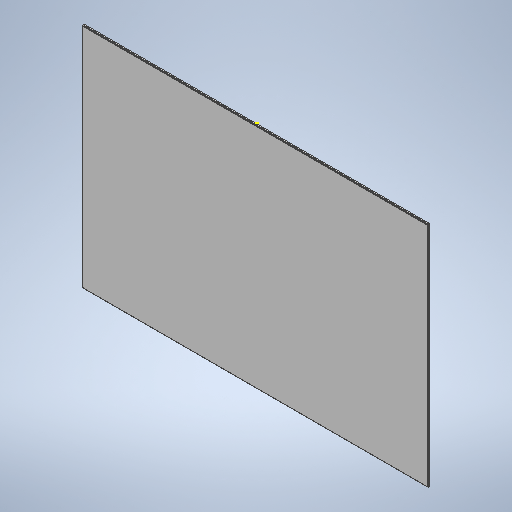
# Autodesk Inventor part: Tampa
Saved by Autodesk Inventor 2025.1 (Build 291241020, 241B)
## iProperties
Created: 2024-11-19
Part Number: Tampa
Material: Genérico
Document SubType Name: Modeling
Designer: Alecs
Density: 1 g/cm^3
Appearance: Padrão
Author: Alecs
Autodesk Inventor part; units mm, degrees
ref_plane "YZ Plane" through (0, 0, 0) normal (1, 0, 0) x (0, 1, 0)
ref_plane "XZ Plane" through (0, 0, 0) normal (0, 1, 0) x (-1, 0, 0)
ref_plane "XY Plane" through (0, 0, 0) normal (0, 0, 1) x (1, 0, 0)
sketch "Esboço1" plane through (0, 0, 0) normal (0, 0, 1) x (1, 0, 0)
  line L0 (322.5, 212.5) -> (-322.5, 212.5)
  line L1 (-322.5, 212.5) -> (-322.5, -212.5)
  line L2 (-322.5, -212.5) -> (322.5, -212.5)
  line L3 (322.5, -212.5) -> (322.5, 212.5)
  line L4 (322.5, 212.5) -> (-322.5, -212.5) construction
  line L5 (-322.5, 212.5) -> (322.5, -212.5) construction
  point P0 (0, 0)
  dimension "d0" = 425
  dimension "d1" = 645
  constraints: 12 end point, 2 midpoint, 2 parallel, 1 horizontal, 1 perpendicular
  measures "d0" distance of L0.end L1.end
  measures "d1" distance of L0.start L0.end
extrude "Extrusão1" add sketch "Esboço1" along normal blind 2
sketch "Esboço2" plane through (0, 0, 2) normal (0, 0, 1) x (1, 0, 0)
  line L0 (320.85, 211) -> (-320.85, 211)
  line L1 (-320.85, 211) -> (-320.85, -211)
  line L2 (-320.85, -211) -> (320.85, -211)
  line L3 (320.85, -211) -> (320.85, 211)
  line L4 (320.85, 211) -> (-320.85, -211) construction
  line L5 (-320.85, 211) -> (320.85, -211) construction
  point P0 (0, 0)
  dimension "d4" = 422
  dimension "d5" = 641.7
  constraints: 12 end point, 2 midpoint, 2 parallel, 1 horizontal, 1 perpendicular
  measures "d4" distance of L0.end L1.end
  measures "d5" distance of L1.end L2.end
extrude "Extrusão2" add sketch "Esboço2" along normal blind 1.175
fillet "Arredondamento1" radius 1 8 edges at (322.5, 212.5, 1) (320.85, 211, 2.5875) (-322.5, 212.5, 1) (-320.85, 211, 2.5875) (322.5, -212.5, 1) (320.85, -211, 2.5875) (-320.85, -211, 2.5875) (-322.5, -212.5, 1)
sketch "Esboço4" plane through (-321.5, 212.5, 0) normal (0, 1, 0) x (1, 0, 0)
  point P0 (321.5, 0)
